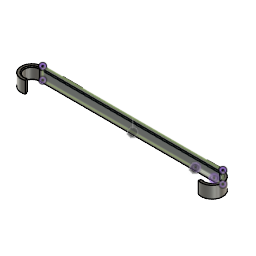
rail (Autodesk Fusion 360 design; units mm, degrees)
part number: 2026-09-13-19-58-23-760
Autodesk Fusion 360 part; units mm, degrees
sketch "Sketch1" plane through (0, 0, 0) normal (0, 0, 1) x (1, 0, 0)
  line L0 (0, 9.5) -> (112.5, 9.5)
  line L1 (0, 0) -> (0, 9.5) construction
  line L2 (112.5, 0) -> (112.5, 9.5) construction
  line L3 (112.5, -40) -> (112.5, 59) construction
  line L4 (0, 13.5) -> (112.5, 13.5)
  line L5 (0, 0) -> (3.2492, -8.9271) construction
  line L6 (0, 0) -> (13.5, 0) construction
  line L7 (3.2492, -8.9271) -> (4.6173, -12.6859)
  arc A0 (4.6173, -12.6859) -> (13.5, 0) centre (0, 0) ccw construction
  arc A1 (3.2492, -8.9271) -> (0, 9.5) centre (0, 0) ccw construction
  arc A2 (0, 9.5) -> (3.2492, -8.9271) centre (0, 0) ccw
  arc A3 (13.5, 0) -> (9.5917, 9.5) centre (0, 0) ccw construction
  arc A4 (0, 13.5) -> (4.6173, -12.6859) centre (0, 0) ccw
  arc A5 (9.5917, 9.5) -> (0, 13.5) centre (0, 0) ccw construction
  line L8 (225, 13.5) -> (112.5, 13.5)
  line L9 (225, 9.5) -> (112.5, 9.5)
  arc A6 (220.3827, -12.6859) -> (225, 13.5) centre (225, 0) ccw
  arc A7 (221.7508, -8.9271) -> (225, 9.5) centre (225, 0) ccw
  line L10 (221.7508, -8.9271) -> (220.3827, -12.6859)
  dimension "d3" = 112.5
  dimension "d103" = 19
  dimension "d105" = 70
  constraint horizontal L0
  constraint perpendicular L0 L3
  constraint coincident L1.start L5.start
  constraint coincident L4.start A3
  constraint coincident L3 L4.end
  constraint perpendicular L3 L4
  constraint horizontal L6
  constraint concentric A1 A3
  constraint concentric A0 A3
  constraint concentric A1 A2
  constraint coincident L0 A3.end
  constraint concentric A3 A4
  constraint concentric A3 A5
  constraint symmetric L0.start L3 L9.start
  constraint symmetric L0.end L3 L2.end
  constraint symmetric L3 L4.start L8.start
  constraint symmetric L3 L4.end L8.end
  constraint symmetric L3 L7.end A6.start
  constraint symmetric L3 L5.end A7.start
  constraint symmetric L3 A2 A7
  constraint symmetric L3 A4 A6
  measures "d3" distance of L0.start L0.end
  measures "d103" diameter of A1
  measures "d105" angle of L5 L6
extrude "Extrude1" add sketch "Sketch1" along normal blind 15
sketch "Sketch7" plane through (0, 13.5, 0) normal (0, 1, 0) x (-1, 0, 0)
  line L0 (-225, 0) -> (0, 0)
  line L1 (0, 0) -> (0, 15)
  line L2 (0, 15) -> (-225, 15)
  line L3 (-225, 15) -> (-225, 0)
  line L4 (-215, 2) -> (-190, 2)
  line L5 (-190, 2) -> (-190, 0)
  line L6 (-190, 0) -> (-215, 0)
  line L7 (-215, 0) -> (-215, 2)
  line L8 (-225, 0) -> (0, 0)
  line L9 (0, 0) -> (0, 15)
  line L10 (0, 15) -> (-225, 15)
  line L11 (-225, 15) -> (-225, 0)
  dimension "d106" = 2
  dimension "d107" = 10
  dimension "d108" = 25
  constraint horizontal L4
  constraint vertical L5
  constraint horizontal L6
  constraint vertical L7
  constraint coincident L0 L5.end
  measures "d106" distance of L4.start L6.end
  measures "d107" distance of L3 L7
  measures "d108" distance of L5.end L6.end
extrude "Extrude6" add sketch "Sketch7" along normal blind 15 contours L0 L4 L5 L6 L7 L8
fillet "Fillet2" radius 1 4 edges at (215, 21, 2) (215, 21, 0) (190, 21, 2) (190, 21, 0)
chamfer "Chamfer1" distance 0.5 distance2 2 4 edges at (202.5, 28.5, 2) (215, 28.5, 1) (202.5, 28.5, 0) (190, 28.5, 1) measured on face at (206.3334, 28.5, 0.6667) measured on face at (215, 18.5, 0.9999) measured on face at (206.3334, 28.5, 0.6667) measured on face at (190, 18.5, 1.0001) tangent chain off
sketch "Sketch9" plane through (0, 13.5, 0) normal (0, 1, 0) x (-1, 0, 0)
  line L0 (-191, 0) -> (0, 0)
  line L1 (0, 0) -> (0, 15)
  line L2 (0, 15) -> (-225, 15)
  line L3 (-225, 15) -> (-225, 0)
  line L4 (-225, 0) -> (-214, 0)
  arc A0 (-214, 2) -> (-214, 0) centre (-214, 1) ccw
  line L5 (-214, 2) -> (-191, 2)
  arc A1 (-191, 0) -> (-191, 2) centre (-191, 1) ccw
  line L6 (-112.5, 15) -> (-112.5, 0) construction
  line L7 (-191, 0) -> (0, 0)
  line L8 (0, 0) -> (0, 15)
  line L9 (0, 15) -> (-225, 15)
  line L10 (-225, 15) -> (-225, 0)
  line L11 (-225, 0) -> (-214, 0)
  arc A2 (-214, 2) -> (-214, 0) centre (-214, 1) ccw
  line L12 (-214, 2) -> (-191, 2)
  arc A3 (-191, 0) -> (-191, 2) centre (-191, 1) ccw
  constraint midpoint L2 L6.start
  constraint coincident L0 L6.end
  constraint perpendicular L0 L6
ref_plane "WorkPlane7" through (112.5, 13.5, 7.5) normal (1, 0, 0) x (0, 0, -1)
mirror "Mirror5" about plane through (112.5, 13.5, 7.5) normal (1, 0, 0) of "Extrude6", "Fillet2"
chamfer "Chamfer3" distance 2 distance2 0.5 4 edges at (22.5, 28.5, 2) (10, 28.5, 1) (22.5, 28.5, 0) (35, 28.5, 1) measured on face at (18.6666, 18.5, 2) measured on face at (10, 18.5, 0.9999) measured on face at (26.3334, 18.5, 0) measured on face at (35, 18.5, 1.0001) tangent chain off
chamfer "Chamfer4" distance 1 angle 45 9 edges at (168.75, 9.5, 15) (56.25, 9.5, 15) (56.25, 9.5, 15) (-9.3557, -1.6497, 15) (234.3557, -1.6497, 15) (168.75, 9.5, 0) (234.3557, -1.6497, 0) (-9.3557, -1.6497, 0) (56.25, 9.5, 0) tangent chain off
